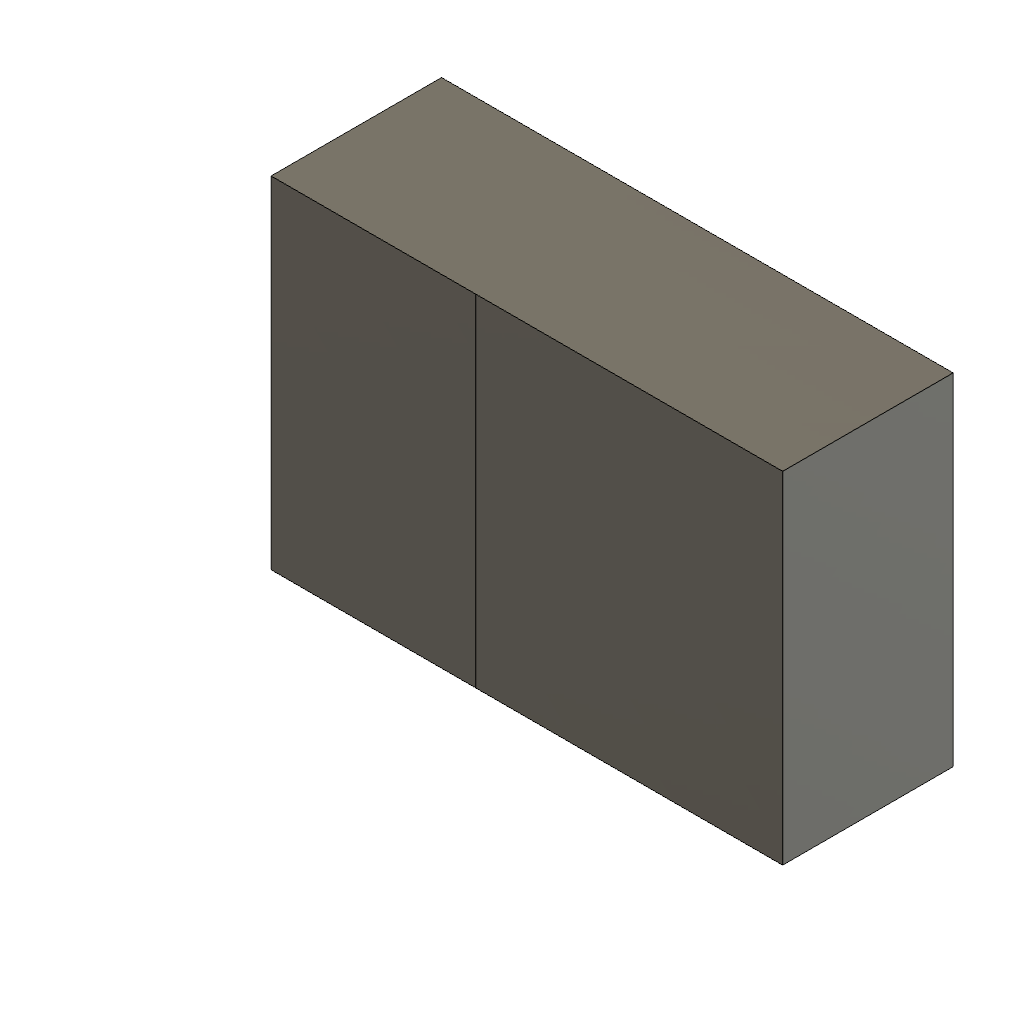
plane (Autodesk Fusion 360 design; units mm, degrees)
part number: 2026-10-20-21-44-41-102
Autodesk Fusion 360 part; units mm, degrees
sketch "TargetProfile" plane through (0, 0, 0) normal (0, 0, 1) x (1, 0, 0)
  line L0 (0, 0) -> (30, 0)
  line L1 (30, 0) -> (30, 20)
  line L2 (30, 20) -> (0, 20)
  line L3 (0, 20) -> (0, 0)
extrude "TargetExtrusion" add sketch "TargetProfile" along normal blind 10
ref_plane "WorkPlane1" through (12, 0, 0) normal (1, 0, 0) x (0, 1, 0)
split_face "ProbeSplitFace" 1 faces at (10, 13.3333, 10) by plane through (12, 0, 0) normal (1, 0, 0)
named bodies: "TargetBody"
